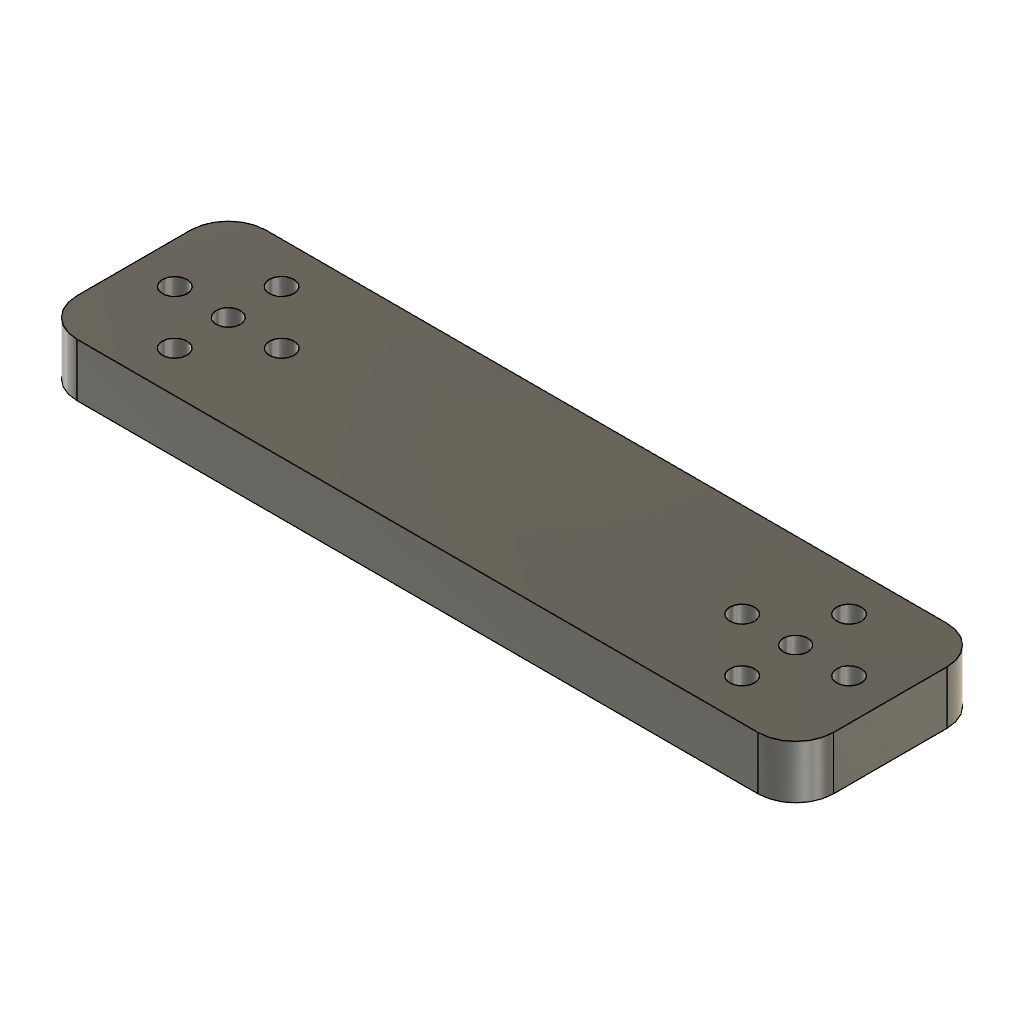
crosshead (Autodesk Fusion 360 design; units mm, degrees)
part number: 2026-11-09-15-51-23-478
Autodesk Fusion 360 part; units mm, degrees
sketch "Sketch1" plane through (0, 0, 0) normal (0, 0, 1) x (1, 0, 0)
  line L0 (0, 2.54) -> (254, 2.54)
  line L1 (254, 2.54) -> (254, 53.34)
  line L2 (254, 53.34) -> (0, 53.34)
  line L3 (0, 53.34) -> (0, 2.54)
  constraint horizontal L0
  constraint vertical L1
  constraint horizontal L2
  constraint vertical L3
extrude "Extrude1" add sketch "Sketch1" along normal blind 14.303
sketch "Sketch2" plane through (0, 0, 14.303) normal (0, 0, 1) x (-1, 0, 0)
  line L0 (0, -53.34) -> (0, -2.54)
  line L1 (0, -2.54) -> (-254, -2.54)
  line L2 (-254, -2.54) -> (-254, -53.34)
  line L3 (-254, -53.34) -> (0, -53.34)
  line L4 (-50.8, -27.94) -> (-127, -27.94)
  line L5 (-127, -27.94) -> (-203.2, -27.94)
  point P0 (-127, -27.94)
  point P1 (-50.8, -27.94)
  point P2 (-203.2, -27.94)
  point P3 (-36.449, -27.94)
  point P4 (-50.7527, -13.5891)
  point P5 (-50.7527, -42.2909)
  point P6 (-217.551, -27.94)
  point P7 (-203.2, -42.291)
  point P8 (-203.2, -13.589)
  point P9 (-188.849, -27.94)
  point P10 (-65.151, -27.94)
  dimension "d5" = 76.2
  dimension "d14" = 14.351
  constraint coincident P1 L4.start
  constraint coincident P0 L4.end
  constraint coincident P2 L5.end
  constraint horizontal L5
  constraint equal L4 L5
  constraint coincident L5 P9
  constraint coincident L4 P10
  measures "d5" distance of P1 P0
  measures "d14" distance of P1 P3
hole "Hole1" at (50.8, 27.94, 14.303) at (203.2, 27.94, 14.303) at (203.2, 27.94, 14.303) direction (0, 0, -1) diameter 6.477 end through all
hole "Hole2" at (36.449, 27.94, 14.303) at (50.7527, 42.2909, 14.303) at (65.151, 27.94, 14.303) at (50.7527, 13.5891, 14.303) at (188.849, 27.94, 14.303) at (203.2, 42.291, 14.303) at (217.551, 27.94, 14.303) at (203.2, 13.589, 14.303) direction (0, 0, -1) diameter 6.604 depth 6.7564 tip angle 180
fillet "Fillet1" radius 10.16 4 edges at (254, 2.54, 7.1515) (254, 53.34, 7.1515) (0, 2.54, 7.1515) (0, 53.34, 7.1515)
sketch "Sketch3" plane through (0, 0, 14.303) normal (0, 0, 1) x (-1, 0, 0)
  line L0 (-50.8, -27.94) -> (-127, -27.94)
  line L1 (-127.0134, -37.84) -> (-127.0134, -16.7936) construction
  line L2 (-25.4, 6.2939) -> (12.6979, 6.2939)
  line L3 (12.6979, 6.2939) -> (12.6979, -62.1739)
  line L4 (12.6979, -62.1739) -> (-25.4, -62.1739)
  line L5 (-25.4, -62.1739) -> (-25.4, 6.2939)
  line L6 (-228.6268, -62.1739) -> (-228.6268, 6.2939)
  line L7 (-228.6268, 6.2939) -> (-266.7247, 6.2939)
  line L8 (-266.7247, 6.2939) -> (-266.7247, -62.1739)
  line L9 (-266.7247, -62.1739) -> (-228.6268, -62.1739)
  point P0 (-127, -27.94)
  point P1 (-25.4, -27.94)
  dimension "d29" = 101.6
  constraint perpendicular L0 L1
  constraint horizontal L2
  constraint vertical L3
  constraint horizontal L4
  constraint vertical L5
  constraint midpoint L5 P1
  constraint horizontal P0 P1
  constraint symmetric L1 L2.start L6.end
  constraint symmetric L1 L2.end L7.end
  constraint symmetric L1 L3.end L8.end
  constraint symmetric L1 L4.end L6.start
  measures "d29" distance of P0 P1
extrude "Extrude3" cut sketch "Sketch3" against normal blind 25.4
fillet "Fillet3" radius 10.16 4 edges at (25.4, 53.34, 7.1515) (25.4, 2.54, 7.1515) (228.6268, 2.54, 7.1515) (228.6268, 53.34, 7.1515)
equation "h = ( ( ( w * length ^ 3 ) / ( 32 * e * def * depth ) ) ^ ( 1 / 3 ) ) * 1 in"
equation "L = 10 in"
equation "D = 2 in"
equation "def = ( 0.00393701 in ) / in"
equation "SF = 4"
equation "e = ( 9993.1 ksi ) / ksi"
equation "w = 0.4496"
equation "length = ( 10 in ) / in"
equation "depth = ( 2 in ) / in"
